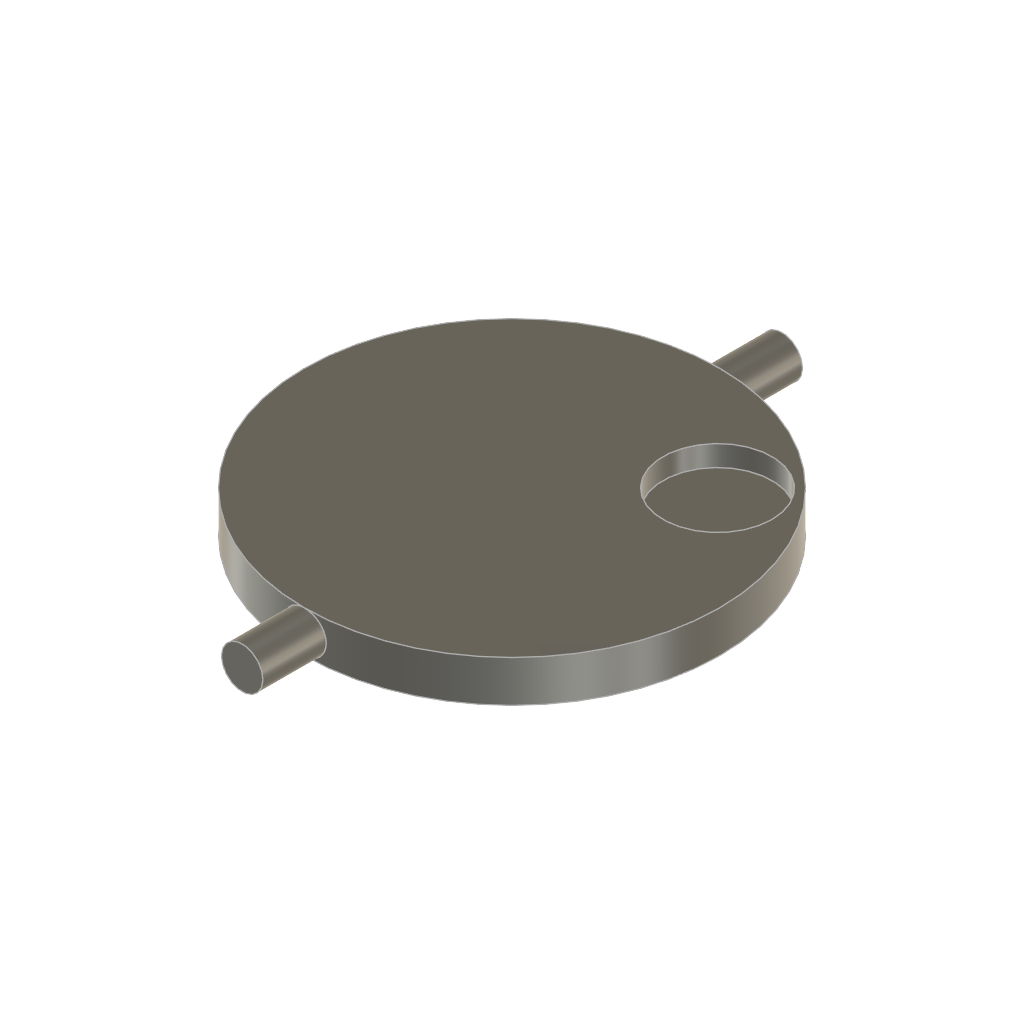
coin_dot (Autodesk Fusion 360 design; units mm, degrees)
Autodesk Fusion 360 part; units mm, degrees
sketch " MainBody" plane through (0, 0, 0) normal (0, 0, 1) x (1, 0, 0)
  circle A0 centre (0, 0) radius 10
  dimension "d1" = 20
  constraint coincident A0.centre origin
  measures "d1" diameter of A0
extrude "Extrude1" add sketch " MainBody" along normal blind 2 makes body 1
sketch "Posts" plane through (0, 0, 0) normal (0, 1, 0) x (1, 0, 0)
  circle A0 centre (0, -1) radius 1
  dimension "d5" = 2
  measures "d5" diameter of A0
extrude "Extrude2" add sketch "Posts" along normal blind 13 and the other way blind 13 separate body makes body 2
combine "Combine1" operation add target body 1 tool bodies 2
sketch "Sketch8" plane through (0, 0, 0) normal (0, 0, 1) x (1, 0, 0)
  line L0 (0, 0) -> (4.9497, 4.9497) construction
  line L1 (0, 0) -> (6, 0) construction
  dimension "d19" = 7
  dimension "d20" = 45
  constraint horizontal L1
  constraint coincident L0.start L1.start
  measures "d19" distance of L0.start L0.end
  measures "d20" angle of L0 L1
sketch "Sketch9" plane through (0, 0, 2) normal (0, 0, 1) x (-1, 0, 0)
  circle A0 centre (-4.9497, -4.9497) radius 2.625
  point P0 (-4.9497, -4.9497)
  dimension "d21" = 5.25
  constraint coincident P0 A0.centre
  measures "d21" diameter of A0
extrude "Extrude5" cut sketch "Sketch9" against normal blind 1 bodies 1
